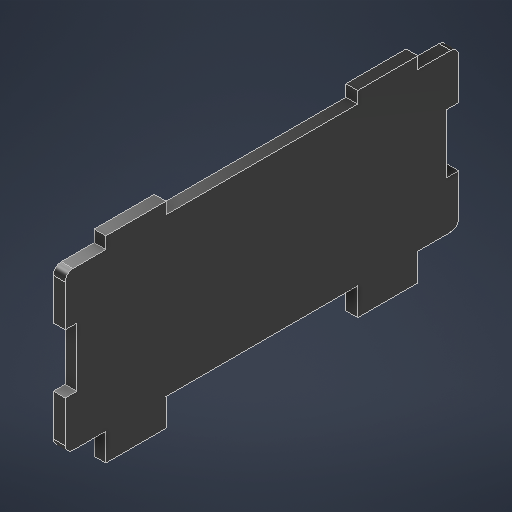
# Autodesk Inventor part: SideFace
Saved by Autodesk Inventor 2027.1 (Build 311270010, 270A)
## iProperties
Created: 2026-10-18
Part Number: SideFace
Material: MDF Medium Density Fiberboard
Document SubType Name: Modeling
Designer: SDS Scholar
Density: 0.8 g/cm^3
Appearance: Glossy - Black
Mass: 10.164 g
Surface Area: 95.4823 cm^2
Volume: 12.705 cm^3
Author: SDS Scholar
Autodesk Inventor part; units mm, degrees
ref_plane "YZ Plane" through (0, 0, 0) normal (1, 0, 0) x (0, 1, 0)
ref_plane "XZ Plane" through (0, 0, 0) normal (0, 1, 0) x (-1, 0, 0)
ref_plane "XY Plane" through (0, 0, 0) normal (0, 0, 1) x (1, 0, 0)
sketch "Sketch1" plane through (0, 0, 0) normal (1, 0, 0) x (0, 1, 0)
  line L0 (20, 50) -> (-20, 50)
  line L1 (-20, 50) -> (-20, -50)
  line L2 (-20, -50) -> (20, -50)
  line L3 (20, -50) -> (20, 50)
  line L4 (20, 0) -> (-20, 0) construction
  line L5 (20, 47) -> (-20, 47) construction
  line L6 (20, 17) -> (-20, 17) construction
  line L7 (20, 39.65) -> (23, 39.65)
  line L8 (23, 39.65) -> (23, 24.35)
  line L9 (23, 24.35) -> (20, 24.35)
  line L10 (20, 24.35) -> (20, 39.65)
  line L11 (0, 47) -> (0, 17) construction
  line L12 (20, 14) -> (-20, 14) construction
  line L13 (20, -47) -> (-20, -47) construction
  line L14 (-20, 39.65) -> (-27, 39.65)
  line L15 (-27, 39.65) -> (-27, 24.35)
  line L16 (-27, 24.35) -> (-20, 24.35)
  line L17 (-20, 24.35) -> (-20, 39.65)
  line L18 (-20, 50) -> (-20, 0) construction
  line L19 (20, -39.65) -> (23, -39.65)
  line L20 (23, -39.65) -> (23, -24.35)
  line L21 (23, -24.35) -> (20, -24.35)
  line L22 (-20, -39.65) -> (-27, -39.65)
  line L23 (-27, -39.65) -> (-27, -24.35)
  line L24 (-27, -24.35) -> (-20, -24.35)
  line L25 (-20, -24.35) -> (-20, -39.65)
  point P0 (0, 0)
  point P1 (0, -50)
  point P2 (23, 32)
  point P3 (0, 32)
  point P4 (0, 47)
  point P5 (-20, 25)
  point P6 (-20, 24.35)
  point P7 (20, -24.35)
  point P8 (20, -39.65)
  point P9 (20, 24.35)
  point P10 (-20, -24.35)
  point P11 (-27, 32)
  point P12 (-27, -32)
  dimension "d0" = 40
  dimension "d1" = 100
  dimension "d12" = 3
  dimension "d13" = 30
  dimension "d14" = 15.3
  dimension "d15" = 3
  dimension "d16" = 3
  dimension "d17" = 3
  dimension "d18" = 15.3
  dimension "d19" = 7
  dimension "d23" = 15.3
  dimension "d24" = 7
  dimension "d25" = 10.35
  dimension "d26" = 64
  constraints: 50 end point, 10 midpoint, 9 horizontal, 7 parallel, 7 point on line, 5 perpendicular, 4 symmetric about line, 2 horizontal alignment, 2 vertical alignment, 1 coincident, 1 vertical, 10 other
  measures "d0" distance of L0.start L0.end
  measures "d1" distance of L0.end L2.start
  measures "d12" distance between parallel lines of L0 L5
  measures "d13" distance between parallel lines of L5 L6
  measures "d14" distance of L7.end L8.end
  measures "d15" distance of L7.start L7.end
  measures "d16" distance between parallel lines of L6 L12
  measures "d17" distance between parallel lines of L2 L13
  measures "d18" distance of L14.end L15.end
  measures "d19" distance of L14.start L14.end
  measures "d23" distance of L22.end L23.end
  measures "d24" distance of L22.start L22.end
  measures "d25" distance between parallel lines of L0 L14
  measures "d26" distance of point (-27, 32) point (-27, -32)
extrude "Extrusion1" add sketch "Sketch1" along normal blind 3
sketch "Sketch2" plane through (3, 0, 0) normal (1, 0, 0) x (0, 0, -1)
  line L0 (-47, 7.65) -> (-47, -7.65) projected
  line L1 (-17, 7.65) -> (-17, -7.65) projected
  line L2 (-14, 7.65) -> (-14, -7.65) projected
  line L3 (47, -7.65) -> (47, 7.65) projected
  line L4 (-47, -7.65) -> (-50, -7.65)
  line L5 (-50, 20) -> (-50, -20) projected
  line L6 (-50, 7.5) -> (-47, 7.5)
  line L7 (-47, 7.5) -> (-47, -7.5)
  line L8 (-47, -7.5) -> (-50, -7.5)
  line L9 (-50, -7.5) -> (-50, 7.5)
  line L10 (50, 7.5) -> (47, 7.5)
  line L11 (47, 7.5) -> (47, -7.5)
  line L12 (47, -7.5) -> (50, -7.5)
  line L13 (50, -7.5) -> (50, 7.5)
  point P0 (-47, 0)
  point P1 (-47, 0)
  point P2 (-50, 0)
  point P3 (47, 0)
  dimension "d4" = 3
  dimension "d5" = 15
  dimension "d8" = 3
  dimension "d9" = 15
  constraints: 18 end point, 6 midpoint, 4 parallel, 3 horizontal, 2 perpendicular, 1 coincident, 1 point on line
  measures "d4" distance of L6.start L6.end
  measures "d5" distance of L6.end L7.end
  measures "d8" distance of L10.start L10.end
  measures "d9" distance of L12.end L10.start
extrude "Extrusion2" cut sketch "Sketch2" against normal through all contours L0 L8 L5 L6 | L3 L10 L13 L12
fillet "Fillet1" radius 2 4 edges at (1.5, 20, 50) (1.5, 20, -50) (1.5, -20, 50) (1.5, -20, -50)
fillet "Fillet2" [suppressed]
equation "\"d0\" = ProductBaseHeight"
equation "\"d1\" = TransmitterAreaWidth"
equation "\"d19\" = BaseWoodThickness"
equation "\"ProductBaseHeight\" = 40"
equation "\"GridProcutClearance\" = 5"
equation "\"GridBorderThickness\" = 5"
equation "\"GridBorderFillets\" = 7"
equation "\"GridTotalSize\" = 65"
equation "\"GridRobotClearance\" = 65"
equation "\"AluminiumExtrusionClearance\" = 35"
equation "\"BaseTotalLength\" = 885"
equation "\"WorkspaceLength\" = 515"
equation "\"WorkspaceHeight\" = 183"
equation "\"AxesBaseFillet\" = 15"
equation "\"Zaxis\" = 197"
equation "\"ProductTotalHeight\" = 45"
equation "\"VerticalStroke\" = 105"
equation "\"BackArea\" = 165"
equation "\"CylinderStroke\" = 75"
equation "\"BoxesWidth\" = 125"
equation "\"BaseWoodThickness\" = 7"
equation "\"Kerf\" = 0.3"
equation "\"TransmitterAreaWidth\" = 100"
equation "\"RxThickness\" = 1.8"
equation "\"support_2\" = 265"
body "Solid1"
